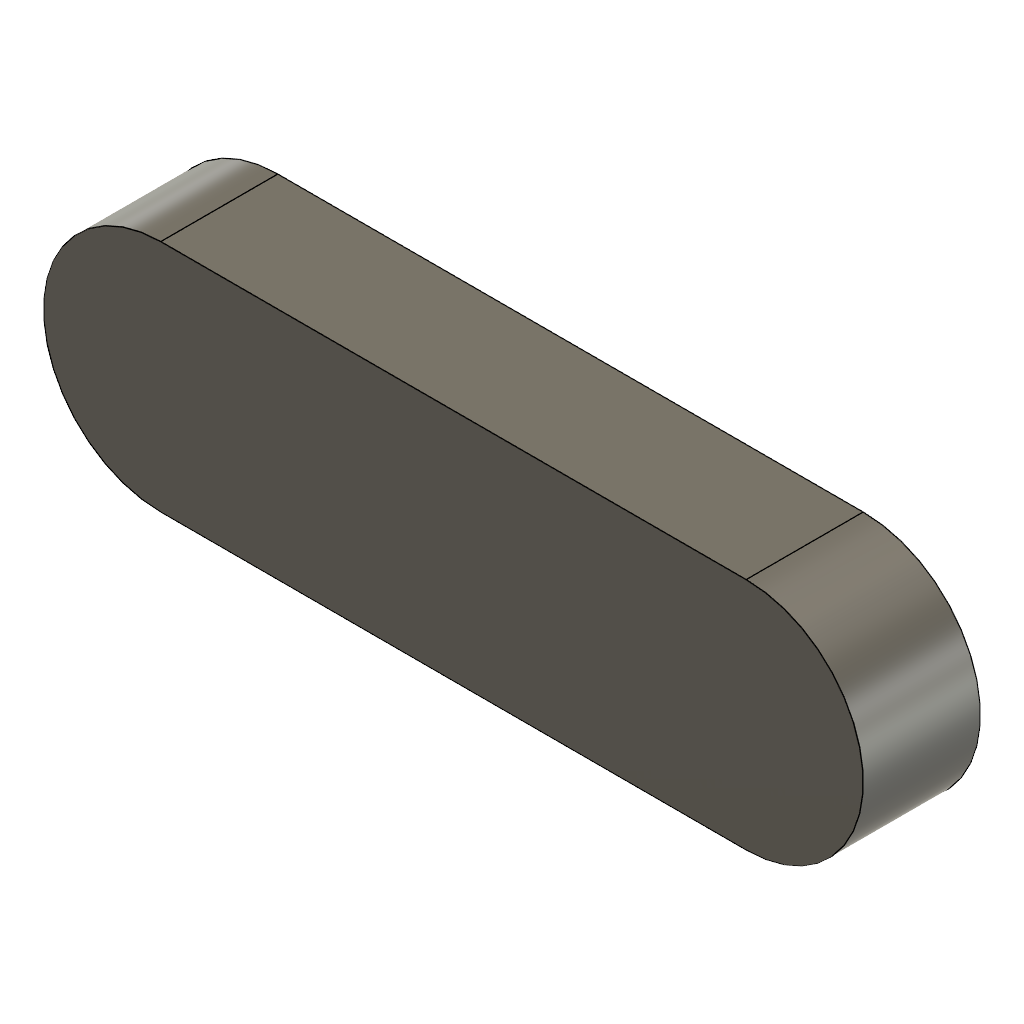
sk_slot_center_to_center (Autodesk Fusion 360 design; units mm, degrees)
part number: 2026-11-13-14-34-51-326
Autodesk Fusion 360 part; units mm, degrees
sketch "Sketch1" plane through (0, 0, 0) normal (0, 0, 1) x (1, 0, 0)
  line L0 (0, -4) -> (20, -4)
  arc A0 (20, -4) -> (20, 4) centre (20, 0) ccw
  line L1 (20, 4) -> (0, 4)
  arc A1 (0, 4) -> (0, -4) centre (0, 0) ccw
  line L2 (0, 0) -> (20, 0) construction
  constraint tangent L0 A0
  constraint tangent A0 L1
  constraint tangent L1 A1
  constraint tangent L0 A1
  constraint parallel L0 L1
extrude "Extrude1" add sketch "Sketch1" along normal blind 4
